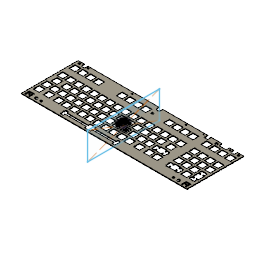
plate (Autodesk Fusion 360 design; units mm, degrees)
part number: 2025-11-08-14-59-07-070
Autodesk Fusion 360 part; units mm, degrees
(part 1 of 2)
sketch "Plate" plane through (0, 0, 0) normal (0, 0, 1) x (1, 0, 0)
  line L0 (-101.0811, -46.4126) -> (-100.2556, -46.4126)
  line L1 (-96.8806, -39.1822) -> (-96.8808, -52.6823) construction
  line L2 (-189.9049, -57.8388) -> (-189.9049, 79.958)
  line L3 (-93.5059, -43.6124) -> (-93.5059, -40.3822)
  line L4 (-100.2556, -43.6124) -> (-101.0811, -43.6124)
  line L5 (211.581, 79.958) -> (211.581, -57.8388)
  line L6 (-100.2556, -40.3822) -> (-100.2556, -43.6124)
  line L7 (-101.0811, -43.6124) -> (-101.0811, -46.4126)
  line L8 (-93.5059, -48.2122) -> (-41.481, -48.2122)
  line L9 (-41.481, -43.6124) -> (-93.5059, -43.6124)
  line L10 (25.094, -43.6124) -> (-27.3319, -43.6124)
  line L11 (-189.9049, 79.958) -> (211.581, 79.958)
  line L12 (211.581, -57.8388) -> (-189.9049, -57.8388)
  line L13 (198.458, -33.4383) -> (201.255, -33.4383)
  line L14 (196.659, -24.4124) -> (196.659, -25.8632)
  line L15 (107.469, -2.2824) -> (107.469, -5.5124)
  line L16 (192.185, -25.8632) -> (192.185, -27.5872)
  line L17 (190.986, -30.8876) -> (192.185, -30.8876)
  line L18 (204.487, -32.6129) -> (204.487, -25.8632)
  line L19 (201.255, -33.4383) -> (201.255, -32.6129)
  line L20 (115.044, -5.5124) -> (114.22, -5.5124)
  line L21 (107.469, -5.5124) -> (106.0178, -5.5124)
  line L22 (196.659, -8.8126) -> (196.659, -10.2624)
  line L23 (136.056, -33.6326) -> (137.782, -33.6326)
  line L24 (90.42, -10.1123) -> (91.8678, -10.1123)
  line L25 (135.231, -27.3626) -> (136.056, -27.3626)
  line L26 (144.2558, -24.5624) -> (142.806, -24.5624)
  line L27 (106.0178, -10.1123) -> (107.469, -10.1123)
  line L28 (204.487, -25.8632) -> (201.255, -25.8632)
  line L29 (115.044, -8.3124) -> (115.044, -5.5124)
  line L30 (31.844, -43.6124) -> (31.844, -40.3822)
  line L31 (28.469, -52.6826) -> (28.4695, -39.1822) construction
  line L32 (114.22, -2.2824) -> (107.469, -2.2824)
  line L33 (114.22, -5.5124) -> (114.22, -2.2824)
  line L34 (31.844, -46.4126) -> (32.67, -46.4126)
  line L35 (114.22, -8.3124) -> (115.044, -8.3124)
  line L36 (31.844, -52.6826) -> (31.844, -46.4126)
  line L37 (107.469, -10.1123) -> (107.469, -14.5827)
  line L38 (83.67, -2.2824) -> (83.67, -5.5124)
  line L39 (-184.3561, -19.7884) -> (-170.2053, -19.7884)
  line L40 (85.394, -14.5827) -> (85.394, -15.7828)
  line L41 (192.185, -30.8876) -> (192.185, -32.6129)
  line L42 (190.986, -27.5872) -> (190.986, -30.8876)
  line L43 (167.431, -27.3626) -> (167.431, -24.5624)
  line L44 (167.431, -24.5624) -> (166.605, -24.5624)
  line L45 (136.056, -24.5624) -> (135.231, -24.5624)
  line L46 (190.986, -3.787) -> (190.986, -7.0876)
  line L47 (161.582, -33.6326) -> (161.582, -34.8329)
  line L48 (141.082, -33.6326) -> (142.806, -33.6326)
  line L49 (142.806, -33.6326) -> (142.806, -29.1622)
  line L50 (198.458, -1.2378) -> (198.458, -2.0633)
  line L51 (85.394, -15.7828) -> (88.694, -15.7828)
  line L52 (25.094, -48.2122) -> (25.094, -52.6826)
  line L53 (88.694, -15.7828) -> (88.694, -14.5827)
  line L54 (141.082, -34.8329) -> (141.082, -33.6326)
  line L55 (82.845, -5.5124) -> (82.845, -8.3124)
  line L56 (192.185, -7.0876) -> (192.185, -8.8126)
  line L57 (136.056, -27.3626) -> (136.056, -33.6326)
  line L58 (135.231, -24.5624) -> (135.231, -27.3626)
  line L59 (32.67, -43.6124) -> (31.844, -43.6124)
  line L60 (32.67, -46.4126) -> (32.67, -43.6124)
  line L61 (112.495, -14.5827) -> (114.22, -14.5827)
  line L62 (90.42, -2.2824) -> (83.67, -2.2824)
  line L63 (201.255, -1.2378) -> (198.458, -1.2378)
  line L64 (107.469, -14.5827) -> (109.194, -14.5827)
  line L65 (204.487, -8.8126) -> (204.487, -2.0633)
  line L66 (201.255, -10.2624) -> (201.255, -8.8126)
  line L67 (159.856, -21.3324) -> (159.856, -24.5624)
  line L68 (161.582, -34.8329) -> (164.88, -34.8329)
  line L69 (90.42, -14.5827) -> (90.42, -10.1123)
  line L70 (88.694, -14.5827) -> (90.42, -14.5827)
  line L71 (83.67, -8.3124) -> (83.67, -14.5827)
  line L72 (90.42, -5.5124) -> (90.42, -2.2824)
  line L73 (-184.3562, -33.9378) -> (-184.3561, -19.7884)
  line L74 (201.255, -32.6129) -> (204.487, -32.6129)
  line L75 (190.986, -7.0876) -> (192.185, -7.0876)
  line L76 (166.605, -24.5624) -> (166.605, -21.3324)
  line L77 (91.8678, -5.5124) -> (90.42, -5.5124)
  line L78 (192.185, -32.6129) -> (198.458, -32.6129)
  line L79 (201.255, -8.8126) -> (204.487, -8.8126)
  line L80 (166.605, -27.3626) -> (167.431, -27.3626)
  line L81 (198.458, -32.6129) -> (198.458, -33.4383)
  line L82 (198.458, -2.0633) -> (192.185, -2.0633)
  line L83 (166.605, -21.3324) -> (159.856, -21.3324)
  line L84 (196.659, -25.8632) -> (192.185, -25.8632)
  line L85 (114.22, -14.5827) -> (114.22, -8.3124)
  line L86 (109.194, -14.5827) -> (109.194, -15.7828)
  line L87 (166.605, -33.6326) -> (166.605, -27.3626)
  line L88 (142.806, -21.3324) -> (136.056, -21.3324)
  line L89 (204.487, -2.0633) -> (201.255, -2.0633)
  line L90 (192.185, -27.5872) -> (190.986, -27.5872)
  line L91 (137.782, -33.6326) -> (137.782, -34.8329)
  line L92 (164.88, -34.8329) -> (164.88, -33.6326)
  line L93 (192.185, -8.8126) -> (196.659, -8.8126)
  line L94 (201.255, -2.0633) -> (201.255, -1.2378)
  line L95 (25.094, -40.3822) -> (25.094, -43.6124)
  line L96 (159.856, -29.1622) -> (159.856, -33.6326)
  line L97 (159.856, -33.6326) -> (161.582, -33.6326)
  line L98 (136.056, -21.3324) -> (136.056, -24.5624)
  line L99 (112.495, -15.7828) -> (112.495, -14.5827)
  line L100 (201.255, -25.8632) -> (201.255, -24.4124)
  line L101 (137.782, -34.8329) -> (141.082, -34.8329)
  line L102 (142.806, -24.5624) -> (142.806, -21.3324)
  line L103 (159.856, -24.5624) -> (158.4058, -24.5624)
  line L104 (142.806, -29.1622) -> (144.2558, -29.1622)
  line L105 (164.88, -33.6326) -> (166.605, -33.6326)
  line L106 (109.194, -15.7828) -> (112.495, -15.7828)
  line L107 (192.185, -3.787) -> (190.986, -3.787)
  line L108 (158.4058, -29.1622) -> (159.856, -29.1622)
  line L109 (83.67, -14.5827) -> (85.394, -14.5827)
  line L110 (192.185, -2.0633) -> (192.185, -3.787)
  line L111 (-100.2556, -46.4126) -> (-100.2556, -52.6823)
  line L112 (-100.2556, -52.6823) -> (-93.5059, -52.6824)
  line L113 (-93.5059, -52.6824) -> (-93.5059, -48.2122)
  line L114 (-170.2053, -33.9378) -> (-184.3562, -33.9378)
  line L115 (82.845, -8.3124) -> (83.67, -8.3124)
  line L116 (83.67, -5.5124) -> (82.845, -5.5124)
  line L117 (-170.2053, -19.7884) -> (-170.2053, -33.9378)
  line L118 (-175.1549, -54.3181) -> (-173.1549, -54.3181)
  line L119 (-173.1549, -43.3181) -> (-173.1549, -54.3181)
  line L120 (-189.9049, 79.958) -> (211.532, 79.958)
  arc A0 (-174.5049, 75.458) -> (-165.5049, 75.458) centre (-170.0049, 75.458) ccw
  circle A1 centre (-182.0049, 74.958) radius 2.5
  line L121 (-165.5049, 75.458) -> (-165.5049, 79.958)
  line L122 (-189.9049, 79.958) -> (211.532, 79.958)
  circle A2 centre (-161.0049, 75.458) radius 1.75
  line L123 (-174.5049, 75.458) -> (-174.5049, 79.958)
  line L124 (-175.1549, -54.3181) -> (-175.1549, -45.3181)
  line L125 (-182.6549, -54.3181) -> (-184.6549, -54.3181)
  line L126 (-184.6549, -43.3181) -> (-173.1549, -43.3181)
  line L127 (-175.1549, -45.3181) -> (-182.6549, -45.3181)
  line L128 (-182.6549, -54.3181) -> (-175.1549, -54.3181) construction
  line L129 (150.132, 70.458) -> (150.132, 75.458)
  line L130 (204.282, -54.3181) -> (204.282, -45.3181)
  line L131 (6.3721, 75.4444) -> (6.4059, 79.958)
  arc A3 (6.3721, 75.4444) -> (15.3719, 75.3774) centre (10.872, 75.4108) ccw
  line L132 (15.3719, 75.3774) -> (15.4059, 79.958)
  circle A4 centre (-178.9049, -49.3181) radius 1.75
  circle A5 centre (-54.2449, 75.458) radius 1.75
  line L133 (-184.6549, -54.3181) -> (-184.6549, -43.3181)
  line L134 (-189.9049, 79.958) -> (211.532, 79.958)
  circle A6 centre (-161.6549, -49.8181) radius 3.25
  line L135 (-189.9049, 79.958) -> (211.532, 79.958)
  line L136 (206.282, -43.3181) -> (206.282, -54.3181)
  circle A7 centre (203.632, 74.958) radius 2.5
  line L137 (187.132, 75.458) -> (187.132, 79.958)
  line L138 (173.632, 71.958) -> (161.632, 71.958)
  arc A8 (187.132, 75.458) -> (196.132, 75.458) centre (191.632, 75.458) ccw
  line L139 (150.132, 75.458) -> (155.132, 75.458)
  arc A9 (173.632, 71.958) -> (176.632, 74.958) centre (173.632, 74.958) ccw
  circle A10 centre (75.872, 75.458) radius 1.75
  line L140 (132.432, 71) -> (124.432, 71)
  line L141 (124.432, 80) -> (132.432, 80)
  line L142 (132.432, 80) -> (132.432, 71)
  circle A11 centre (117.432, 76.708) radius 1.25
  line L143 (155.132, 70.458) -> (150.132, 70.458)
  line L144 (124.432, 71) -> (124.432, 80)
  circle A12 centre (183.282, -49.8181) radius 3.25
  line L145 (176.632, 79.958) -> (176.632, 74.958)
  circle A13 centre (182.632, 75.458) radius 1.75
  line L146 (196.132, 75.458) -> (196.132, 79.958)
  line L147 (158.632, 74.958) -> (158.632, 79.958)
  line L148 (155.132, 75.458) -> (155.132, 70.458)
  arc A14 (158.632, 74.958) -> (161.632, 71.958) centre (161.632, 74.958) ccw
  line L149 (196.782, -54.3181) -> (194.782, -54.3181)
  line L150 (194.782, -43.3181) -> (206.282, -43.3181)
  line L151 (196.782, -45.3181) -> (196.782, -54.3181)
  line L152 (204.282, -45.3181) -> (196.782, -45.3181)
  circle A15 centre (200.532, -49.3181) radius 1.75
  line L153 (-182.6549, -45.3181) -> (-182.6549, -54.3181)
  line L154 (196.782, -54.3181) -> (204.282, -54.3181) construction
  line L155 (206.282, -54.3181) -> (204.282, -54.3181)
  line L156 (194.782, -54.3181) -> (194.782, -43.3181)
  line L157 (-170.2062, 66.925) -> (-184.3562, 66.925)
  line L158 (-184.3562, 66.925) -> (-184.3562, 52.775)
  line L159 (-184.3562, 52.775) -> (-170.2062, 52.775)
  line L160 (-170.2062, 52.775) -> (-170.2062, 66.925)
  line L161 (-170.2062, 66.925) -> (-184.3562, 52.775) construction
  line L162 (-184.3562, 66.925) -> (-170.2062, 52.775) construction
  line L163 (-170.2062, 23.2116) -> (-170.2062, 37.3616)
  line L164 (-184.3562, 37.3616) -> (-184.3562, 23.2116)
  line L165 (-170.2062, 37.3616) -> (-184.3562, 37.3616)
  line L166 (-170.2062, 37.3616) -> (-184.3562, 23.2116) construction
  line L167 (-184.3562, 37.3616) -> (-170.2062, 23.2116) construction
  line L168 (-184.3562, 23.2116) -> (-170.2062, 23.2116)
  line L169 (-179.5739, 18.3116) -> (-165.4239, 4.1616) construction
  line L170 (-165.4239, 18.3116) -> (-179.5739, 4.1616) construction
  line L171 (-179.5739, 4.1616) -> (-165.4239, 4.1616)
  line L172 (-165.4239, 4.1616) -> (-165.4239, 18.3116)
  line L173 (-179.5739, 18.3116) -> (-179.5739, 4.1616)
  line L174 (-165.4239, 18.3116) -> (-179.5739, 18.3116)
  line L175 (-165.3062, 66.925) -> (-165.3062, 52.775)
  line L176 (-151.1562, 66.925) -> (-165.3062, 66.925)
  line L177 (-165.3062, 52.775) -> (-151.1562, 52.775)
  line L178 (-151.1562, 52.775) -> (-151.1562, 66.925)
  line L179 (-165.3062, 66.925) -> (-151.1562, 52.775) construction
  line L180 (-151.1562, 66.925) -> (-165.3062, 52.775) construction
  line L181 (-146.2562, 66.925) -> (-146.2562, 52.775)
  line L182 (-132.1062, 66.925) -> (-146.2562, 66.925)
  line L183 (-146.2562, 52.775) -> (-132.1062, 52.775)
  line L184 (-132.1062, 52.775) -> (-132.1062, 66.925)
  line L185 (-146.2562, 66.925) -> (-132.1062, 52.775) construction
  line L186 (-132.1062, 66.925) -> (-146.2562, 52.775) construction
  line L187 (-127.2062, 66.925) -> (-127.2062, 52.775)
  line L188 (-113.0562, 66.925) -> (-127.2062, 66.925)
  line L189 (-127.2062, 52.775) -> (-113.0562, 52.775)
  line L190 (-113.0562, 52.775) -> (-113.0562, 66.925)
  line L191 (-127.2062, 66.925) -> (-113.0562, 52.775) construction
  line L192 (-113.0562, 66.925) -> (-127.2062, 52.775) construction
  line L193 (-113.0562, 66.925) -> (-127.2062, 66.925)
  line L194 (-127.2062, 52.775) -> (-113.0562, 52.775)
  line L195 (-165.3062, 52.775) -> (-151.1562, 52.775)
  line L196 (-170.2062, 66.925) -> (-184.3562, 66.925)
  line L197 (-151.1562, 66.925) -> (-165.3062, 52.775) construction
  line L198 (-184.3562, 66.925) -> (-184.3562, 52.775)
  line L199 (-132.1062, 66.925) -> (-146.2562, 66.925)
  line L200 (-132.1062, 66.925) -> (-146.2562, 52.775) construction
  line L201 (-146.2562, 66.925) -> (-146.2562, 52.775)
  line L202 (-165.3062, 66.925) -> (-151.1562, 52.775) construction
  line L203 (-127.2062, 66.925) -> (-113.0562, 52.775) construction
  line L204 (-184.3562, 52.775) -> (-170.2062, 52.775)
  line L205 (-165.3062, 66.925) -> (-165.3062, 52.775)
  line L206 (-170.2062, 52.775) -> (-170.2062, 66.925)
  line L207 (-146.2562, 66.925) -> (-132.1062, 52.775) construction
  line L208 (-113.0562, 52.775) -> (-113.0562, 66.925)
  line L209 (-113.0562, 66.925) -> (-127.2062, 52.775) construction
  line L210 (-127.2062, 66.925) -> (-127.2062, 52.775)
  line L211 (-132.1062, 52.775) -> (-132.1062, 66.925)
  line L212 (-146.2562, 52.775) -> (-132.1062, 52.775)
  line L213 (-151.1562, 66.925) -> (-165.3062, 66.925)
  line L214 (-170.2062, 66.925) -> (-184.3562, 52.775) construction
  line L215 (-151.1562, 52.775) -> (-151.1562, 66.925)
  line L216 (-184.3562, 66.925) -> (-170.2062, 52.775) construction
  line L217 (1.2438, 52.775) -> (1.2438, 66.925)
  line L218 (-31.9562, 52.775) -> (-17.8062, 52.775)
  line L219 (1.2438, 66.925) -> (-12.9062, 52.775) construction
  line L220 (-36.8562, 66.925) -> (-51.0062, 52.775) construction
  line L221 (-36.8562, 66.925) -> (-51.0062, 66.925)
  line L222 (-55.9062, 66.925) -> (-70.0562, 66.925)
  line L223 (-55.9062, 52.775) -> (-55.9062, 66.925)
  line L224 (-17.8062, 66.925) -> (-31.9562, 66.925)
  line L225 (-12.9062, 52.775) -> (1.2438, 52.775)
  line L226 (-51.0062, 66.925) -> (-36.8562, 52.775) construction
  line L227 (-51.0062, 52.775) -> (-36.8562, 52.775)
  line L228 (-36.8562, 66.925) -> (-51.0062, 52.775) construction
  line L229 (-51.0062, 66.925) -> (-36.8562, 52.775) construction
  line L230 (-12.9062, 66.925) -> (1.2438, 52.775) construction
  line L231 (-17.8062, 66.925) -> (-31.9562, 66.925)
  line L232 (1.2438, 66.925) -> (-12.9062, 66.925)
  line L233 (-36.8562, 52.775) -> (-36.8562, 66.925)
  line L234 (-70.0562, 52.775) -> (-55.9062, 52.775)
  line L235 (-55.9062, 52.775) -> (-55.9062, 66.925)
  line L236 (-70.0562, 66.925) -> (-70.0562, 52.775)
  line L237 (-36.8562, 52.775) -> (-36.8562, 66.925)
  line L238 (-55.9062, 66.925) -> (-70.0562, 66.925)
  line L239 (-70.0562, 66.925) -> (-70.0562, 52.775)
  line L240 (-51.0062, 66.925) -> (-51.0062, 52.775)
  line L241 (1.2438, 52.775) -> (1.2438, 66.925)
  line L242 (-17.8062, 52.775) -> (-17.8062, 66.925)
  line L243 (-70.0562, 66.925) -> (-55.9062, 52.775) construction
  line L244 (-12.9062, 66.925) -> (1.2438, 52.775) construction
  line L245 (-12.9062, 66.925) -> (-12.9062, 52.775)
  line L246 (-55.9062, 66.925) -> (-70.0562, 52.775) construction
  line L247 (-70.0562, 66.925) -> (-55.9062, 52.775) construction
  line L248 (-55.9062, 66.925) -> (-70.0562, 52.775) construction
  line L249 (-17.8062, 52.775) -> (-17.8062, 66.925)
  line L250 (1.2438, 66.925) -> (-12.9062, 52.775) construction
  line L251 (-12.9062, 52.775) -> (1.2438, 52.775)
  line L252 (-12.9062, 66.925) -> (-12.9062, 52.775)
  line L253 (-31.9562, 66.925) -> (-17.8062, 52.775) construction
  line L254 (-17.8062, 66.925) -> (-31.9562, 52.775) construction
  line L255 (1.2438, 66.925) -> (-12.9062, 66.925)
  line L256 (-17.8062, 66.925) -> (-31.9562, 52.775) construction
  line L257 (-31.9562, 52.775) -> (-17.8062, 52.775)
  line L258 (-31.9562, 66.925) -> (-17.8062, 52.775) construction
  line L259 (-51.0062, 52.775) -> (-36.8562, 52.775)
  line L260 (-70.0562, 52.775) -> (-55.9062, 52.775)
  line L261 (-36.8562, 66.925) -> (-51.0062, 66.925)
  line L262 (-31.9562, 66.925) -> (-31.9562, 52.775)
  line L263 (-51.0062, 66.925) -> (-51.0062, 52.775)
  line L264 (-31.9562, 66.925) -> (-31.9562, 52.775)
  line L265 (115.5438, 52.775) -> (115.5438, 66.925)
  line L266 (82.3438, 52.775) -> (96.4938, 52.775)
  line L267 (115.5438, 66.925) -> (101.3938, 52.775) construction
  line L268 (77.4438, 66.925) -> (63.2938, 52.775) construction
  line L269 (77.4438, 66.925) -> (63.2938, 66.925)
  line L270 (58.3938, 66.925) -> (44.2438, 66.925)
  line L271 (58.3938, 52.775) -> (58.3938, 66.925)
  line L272 (96.4938, 66.925) -> (82.3438, 66.925)
  line L273 (101.3938, 52.775) -> (115.5438, 52.775)
  line L274 (63.2938, 66.925) -> (77.4438, 52.775) construction
  line L275 (63.2938, 52.775) -> (77.4438, 52.775)
  line L276 (77.4438, 66.925) -> (63.2938, 52.775) construction
  line L277 (63.2938, 66.925) -> (77.4438, 52.775) construction
  line L278 (101.3938, 66.925) -> (115.5438, 52.775) construction
  line L279 (96.4938, 66.925) -> (82.3438, 66.925)
  line L280 (115.5438, 66.925) -> (101.3938, 66.925)
  line L281 (77.4438, 52.775) -> (77.4438, 66.925)
  line L282 (44.2438, 52.775) -> (58.3938, 52.775)
  line L283 (58.3938, 52.775) -> (58.3938, 66.925)
  line L284 (44.2438, 66.925) -> (44.2438, 52.775)
  line L285 (77.4438, 52.775) -> (77.4438, 66.925)
  line L286 (58.3938, 66.925) -> (44.2438, 66.925)
  line L287 (44.2438, 66.925) -> (44.2438, 52.775)
  line L288 (63.2938, 66.925) -> (63.2938, 52.775)
  line L289 (115.5438, 52.775) -> (115.5438, 66.925)
  line L290 (96.4938, 52.775) -> (96.4938, 66.925)
  line L291 (44.2438, 66.925) -> (58.3938, 52.775) construction
  line L292 (101.3938, 66.925) -> (115.5438, 52.775) construction
  line L293 (101.3938, 66.925) -> (101.3938, 52.775)
  line L294 (58.3938, 66.925) -> (44.2438, 52.775) construction
  line L295 (44.2438, 66.925) -> (58.3938, 52.775) construction
  line L296 (58.3938, 66.925) -> (44.2438, 52.775) construction
  line L297 (96.4938, 52.775) -> (96.4938, 66.925)
  line L298 (115.5438, 66.925) -> (101.3938, 52.775) construction
  line L299 (101.3938, 52.775) -> (115.5438, 52.775)
  line L300 (101.3938, 66.925) -> (101.3938, 52.775)
  line L301 (82.3438, 66.925) -> (96.4938, 52.775) construction
  line L302 (96.4938, 66.925) -> (82.3438, 52.775) construction
  line L303 (115.5438, 66.925) -> (101.3938, 66.925)
  line L304 (96.4938, 66.925) -> (82.3438, 52.775) construction
  line L305 (82.3438, 52.775) -> (96.4938, 52.775)
  line L306 (82.3438, 66.925) -> (96.4938, 52.775) construction
  line L307 (63.2938, 52.775) -> (77.4438, 52.775)
  line L308 (44.2438, 52.775) -> (58.3938, 52.775)
  line L309 (77.4438, 66.925) -> (63.2938, 66.925)
  line L310 (82.3438, 66.925) -> (82.3438, 52.775)
  line L311 (63.2938, 66.925) -> (63.2938, 52.775)
  line L312 (82.3438, 66.925) -> (82.3438, 52.775)
  line L313 (148.8798, 66.925) -> (134.7298, 66.925)
  line L314 (153.7798, 52.775) -> (167.9298, 52.775)
  line L315 (167.9298, 66.925) -> (153.7798, 52.775) construction
  line L316 (206.0298, 52.775) -> (206.0298, 66.925)
  line L317 (153.7798, 66.925) -> (153.7798, 52.775)
  line L318 (191.8798, 66.925) -> (206.0298, 52.775) construction
  line L319 (186.9798, 52.775) -> (186.9798, 66.925)
  line L320 (191.8798, 66.925) -> (191.8798, 52.775)
  line L321 (153.7798, 66.925) -> (153.7798, 52.775)
  line L322 (153.7798, 66.925) -> (167.9298, 52.775) construction
  line L323 (191.8798, 66.925) -> (206.0298, 52.775) construction
  line L324 (167.9298, 52.775) -> (167.9298, 66.925)
  line L325 (148.8798, 52.775) -> (148.8798, 66.925)
  line L326 (206.0298, 66.925) -> (191.8798, 52.775) construction
  line L327 (172.8298, 66.925) -> (172.8298, 52.775)
  line L328 (167.9298, 52.775) -> (167.9298, 66.925)
  line L329 (206.0298, 66.925) -> (191.8798, 52.775) construction
  line L330 (191.8798, 66.925) -> (191.8798, 52.775)
  line L331 (153.7798, 66.925) -> (167.9298, 52.775) construction
  line L332 (186.9798, 66.925) -> (172.8298, 66.925)
  line L333 (167.9298, 66.925) -> (153.7798, 66.925)
  line L334 (191.8798, 52.775) -> (206.0298, 52.775)
  line L335 (186.9798, 52.775) -> (186.9798, 66.925)
  line L336 (206.0298, 66.925) -> (191.8798, 66.925)
  line L337 (134.7298, 66.925) -> (148.8798, 52.775) construction
  line L338 (206.0298, 52.775) -> (206.0298, 66.925)
  line L339 (186.9798, 66.925) -> (172.8298, 52.775) construction
  line L340 (206.0298, 66.925) -> (191.8798, 66.925)
  line L341 (172.8298, 52.775) -> (186.9798, 52.775)
  line L342 (172.8298, 66.925) -> (186.9798, 52.775) construction
  line L343 (134.7298, 52.775) -> (148.8798, 52.775)
  line L344 (167.9298, 66.925) -> (153.7798, 52.775) construction
  line L345 (148.8798, 52.775) -> (148.8798, 66.925)
  line L346 (134.7298, 66.925) -> (148.8798, 52.775) construction
  line L347 (134.7298, 66.925) -> (134.7298, 52.775)
  line L348 (191.8798, 52.775) -> (206.0298, 52.775)
  line L349 (148.8798, 66.925) -> (134.7298, 52.775) construction
  line L350 (134.7298, 66.925) -> (134.7298, 52.775)
  line L351 (134.7298, 52.775) -> (148.8798, 52.775)
  line L352 (172.8298, 66.925) -> (186.9798, 52.775) construction
  line L353 (148.8798, 66.925) -> (134.7298, 52.775) construction
  line L354 (172.8298, 66.925) -> (172.8298, 52.775)
  line L355 (153.7798, 52.775) -> (167.9298, 52.775)
  line L356 (186.9798, 66.925) -> (172.8298, 52.775) construction
  line L357 (167.9298, 66.925) -> (153.7798, 66.925)
  line L358 (172.8298, 52.775) -> (186.9798, 52.775)
  line L359 (186.9798, 66.925) -> (172.8298, 66.925)
  line L360 (148.8798, 66.925) -> (134.7298, 66.925)
  line L361 (-151.1562, 37.3616) -> (-165.3062, 23.2116) construction
  line L362 (-165.3062, 37.3616) -> (-151.1562, 23.2116) construction
  line L363 (-151.1562, 37.3616) -> (-165.3062, 37.3616)
  line L364 (-165.3062, 23.2116) -> (-151.1562, 23.2116)
  line L365 (-165.3062, 37.3616) -> (-165.3062, 23.2116)
  line L366 (-151.1562, 23.2116) -> (-151.1562, 37.3616)
  line L367 (-132.1062, 37.3616) -> (-146.2562, 23.2116) construction
  line L368 (-146.2562, 37.3616) -> (-132.1062, 23.2116) construction
  line L369 (-132.1062, 37.3616) -> (-146.2562, 37.3616)
  line L370 (-146.2562, 23.2116) -> (-132.1062, 23.2116)
  line L371 (-146.2562, 37.3616) -> (-146.2562, 23.2116)
  line L372 (-132.1062, 23.2116) -> (-132.1062, 37.3616)
  line L373 (-113.0562, 37.3616) -> (-127.2062, 23.2116) construction
  line L374 (-127.2062, 37.3616) -> (-113.0562, 23.2116) construction
  line L375 (-113.0562, 37.3616) -> (-127.2062, 37.3616)
  line L376 (-127.2062, 23.2116) -> (-113.0562, 23.2116)
  line L377 (-127.2062, 37.3616) -> (-127.2062, 23.2116)
  line L378 (-113.0562, 23.2116) -> (-113.0562, 37.3616)
  line L379 (-94.0062, 37.3616) -> (-108.1562, 23.2116) construction
  line L380 (-108.1562, 37.3616) -> (-94.0062, 23.2116) construction
  line L381 (-94.0062, 37.3616) -> (-108.1562, 37.3616)
  line L382 (-108.1562, 23.2116) -> (-94.0062, 23.2116)
  line L383 (-108.1562, 37.3616) -> (-108.1562, 23.2116)
  line L384 (-94.0062, 23.2116) -> (-94.0062, 37.3616)
  line L385 (-74.9562, 37.3616) -> (-89.1062, 23.2116) construction
  line L386 (-89.1062, 37.3616) -> (-74.9562, 23.2116) construction
  line L387 (-74.9562, 37.3616) -> (-89.1062, 37.3616)
  line L388 (-89.1062, 23.2116) -> (-74.9562, 23.2116)
  line L389 (-89.1062, 37.3616) -> (-89.1062, 23.2116)
  line L390 (-74.9562, 23.2116) -> (-74.9562, 37.3616)
  line L391 (-55.9062, 37.3616) -> (-70.0562, 23.2116) construction
  line L392 (-70.0562, 37.3616) -> (-55.9062, 23.2116) construction
  line L393 (-55.9062, 37.3616) -> (-70.0562, 37.3616)
  line L394 (-70.0562, 23.2116) -> (-55.9062, 23.2116)
  line L395 (-70.0562, 37.3616) -> (-70.0562, 23.2116)
  line L396 (-55.9062, 23.2116) -> (-55.9062, 37.3616)
  line L397 (-36.8562, 37.3616) -> (-51.0062, 23.2116) construction
  line L398 (-51.0062, 37.3616) -> (-36.8562, 23.2116) construction
  line L399 (-36.8562, 37.3616) -> (-51.0062, 37.3616)
  line L400 (-51.0062, 23.2116) -> (-36.8562, 23.2116)
  line L401 (-51.0062, 37.3616) -> (-51.0062, 23.2116)
  line L402 (-36.8562, 23.2116) -> (-36.8562, 37.3616)
  line L403 (-17.8062, 37.3616) -> (-31.9562, 23.2116) construction
  line L404 (-31.9562, 37.3616) -> (-17.8062, 23.2116) construction
  line L405 (-17.8062, 37.3616) -> (-31.9562, 37.3616)
  line L406 (-31.9562, 23.2116) -> (-17.8062, 23.2116)
  line L407 (-31.9562, 37.3616) -> (-31.9562, 23.2116)
  line L408 (-17.8062, 23.2116) -> (-17.8062, 37.3616)
  line L409 (1.2438, 37.3616) -> (-12.9062, 23.2116) construction
  line L410 (-12.9062, 37.3616) -> (1.2438, 23.2116) construction
  line L411 (1.2438, 37.3616) -> (-12.9062, 37.3616)
  line L412 (-12.9062, 23.2116) -> (1.2438, 23.2116)
  line L413 (-12.9062, 37.3616) -> (-12.9062, 23.2116)
  line L414 (1.2438, 23.2116) -> (1.2438, 37.3616)
  line L415 (20.2938, 37.3616) -> (6.1438, 23.2116) construction
  line L416 (6.1438, 37.3616) -> (20.2938, 23.2116) construction
  line L417 (20.2938, 37.3616) -> (6.1438, 37.3616)
  line L418 (6.1438, 23.2116) -> (20.2938, 23.2116)
  line L419 (6.1438, 37.3616) -> (6.1438, 23.2116)
  line L420 (20.2938, 23.2116) -> (20.2938, 37.3616)
  line L421 (39.3438, 37.3616) -> (25.1938, 23.2116) construction
  line L422 (25.1938, 37.3616) -> (39.3438, 23.2116) construction
  line L423 (39.3438, 37.3616) -> (25.1938, 37.3616)
  line L424 (25.1938, 23.2116) -> (39.3438, 23.2116)
  line L425 (25.1938, 37.3616) -> (25.1938, 23.2116)
  line L426 (39.3438, 23.2116) -> (39.3438, 37.3616)
  line L427 (58.3938, 37.3616) -> (44.2438, 23.2116) construction
  line L428 (44.2438, 37.3616) -> (58.3938, 23.2116) construction
  line L429 (58.3938, 37.3616) -> (44.2438, 37.3616)
  line L430 (44.2438, 23.2116) -> (58.3938, 23.2116)
  line L431 (44.2438, 37.3616) -> (44.2438, 23.2116)
  line L432 (58.3938, 23.2116) -> (58.3938, 37.3616)
  line L433 (77.4438, 37.3616) -> (63.2938, 23.2116) construction
  line L434 (63.2938, 37.3616) -> (77.4438, 23.2116) construction
  line L435 (77.4438, 37.3616) -> (63.2938, 37.3616)
  line L436 (63.2938, 23.2116) -> (77.4438, 23.2116)
  line L437 (63.2938, 37.3616) -> (63.2938, 23.2116)
  line L438 (77.4438, 23.2116) -> (77.4438, 37.3616)
  line L439 (96.4938, 37.3616) -> (82.3438, 23.2116) construction
  line L440 (82.3438, 37.3616) -> (96.4938, 23.2116) construction
  line L441 (96.4938, 37.3616) -> (82.3438, 37.3616)
  line L442 (82.3438, 23.2116) -> (96.4938, 23.2116)
  line L443 (82.3438, 37.3616) -> (82.3438, 23.2116)
  line L444 (96.4938, 23.2116) -> (96.4938, 37.3616)
  line L445 (115.5438, 37.3616) -> (101.3938, 23.2116) construction
  line L446 (101.3938, 37.3616) -> (115.5438, 23.2116) construction
  line L447 (115.5438, 37.3616) -> (101.3938, 37.3616)
  line L448 (101.3938, 23.2116) -> (115.5438, 23.2116)
  line L449 (101.3938, 37.3616) -> (101.3938, 23.2116)
  line L450 (115.5438, 23.2116) -> (115.5438, 37.3616)
  line L451 (148.8798, 37.3616) -> (134.7298, 23.2116) construction
  line L452 (186.9798, 37.3616) -> (172.8298, 37.3616)
  line L453 (134.7298, 37.3616) -> (148.8798, 23.2116) construction
  line L454 (153.7798, 37.3616) -> (153.7798, 23.2116)
  line L455 (172.8298, 37.3616) -> (186.9798, 23.2116) construction
  line L456 (153.7798, 23.2116) -> (167.9298, 23.2116)
  line L457 (186.9798, 37.3616) -> (172.8298, 23.2116) construction
  line L458 (186.9798, 23.2116) -> (186.9798, 37.3616)
  line L459 (191.8798, 37.3616) -> (191.8798, 23.2116)
  line L460 (206.0298, 23.2116) -> (206.0298, 37.3616)
  line L461 (148.8798, 37.3616) -> (134.7298, 37.3616)
  line L462 (167.9298, 23.2116) -> (167.9298, 37.3616)
  line L463 (191.8798, 23.2116) -> (206.0298, 23.2116)
  line L464 (206.0298, 37.3616) -> (191.8798, 23.2116) construction
  line L465 (153.7798, 37.3616) -> (167.9298, 23.2116) construction
  line L466 (206.0298, 37.3616) -> (191.8798, 37.3616)
  line L467 (191.8798, 37.3616) -> (206.0298, 23.2116) construction
  line L468 (172.8298, 23.2116) -> (186.9798, 23.2116)
  line L469 (134.7298, 23.2116) -> (148.8798, 23.2116)
  line L470 (134.7298, 37.3616) -> (134.7298, 23.2116)
  line L471 (167.9298, 37.3616) -> (153.7798, 23.2116) construction
  line L472 (167.9298, 37.3616) -> (153.7798, 37.3616)
  line L473 (148.8798, 23.2116) -> (148.8798, 37.3616)
  line L474 (172.8298, 37.3616) -> (172.8298, 23.2116)
  line L475 (-155.7819, 18.3116) -> (-155.7819, 4.1616)
  line L476 (-141.6319, 4.1616) -> (-141.6319, 18.3116)
  line L477 (-141.6319, 18.3116) -> (-155.7819, 4.1616) construction
  line L478 (-155.7819, 4.1616) -> (-141.6319, 4.1616)
  line L479 (-141.6319, 18.3116) -> (-155.7819, 18.3116)
  line L480 (-155.7819, 18.3116) -> (-141.6319, 4.1616) construction
  line L481 (-122.5819, 18.3116) -> (-136.7319, 4.1616) construction
  line L482 (-122.5819, 4.1616) -> (-122.5819, 18.3116)
  line L483 (-122.5819, 18.3116) -> (-136.7319, 18.3116)
  line L484 (-136.7319, 4.1616) -> (-122.5819, 4.1616)
  line L485 (-136.7319, 18.3116) -> (-122.5819, 4.1616) construction
  line L486 (-136.7319, 18.3116) -> (-136.7319, 4.1616)
  line L487 (-103.5319, 18.3116) -> (-117.6819, 4.1616) construction
  line L488 (-103.5319, 4.1616) -> (-103.5319, 18.3116)
  line L489 (-103.5319, 18.3116) -> (-117.6819, 18.3116)
  line L490 (-117.6819, 4.1616) -> (-103.5319, 4.1616)
  line L491 (-117.6819, 18.3116) -> (-103.5319, 4.1616) construction
  line L492 (-117.6819, 18.3116) -> (-117.6819, 4.1616)
  line L493 (-84.4819, 18.3116) -> (-98.6319, 4.1616) construction
  line L494 (-84.4819, 4.1616) -> (-84.4819, 18.3116)
  line L495 (-84.4819, 18.3116) -> (-98.6319, 18.3116)
  line L496 (-98.6319, 4.1616) -> (-84.4819, 4.1616)
  line L497 (-98.6319, 18.3116) -> (-84.4819, 4.1616) construction
  line L498 (-98.6319, 18.3116) -> (-98.6319, 4.1616)
  line L499 (-65.4319, 18.3116) -> (-79.5819, 4.1616) construction
  line L500 (-65.4319, 4.1616) -> (-65.4319, 18.3116)
  line L501 (-65.4319, 18.3116) -> (-79.5819, 18.3116)
  line L502 (-79.5819, 4.1616) -> (-65.4319, 4.1616)
  line L503 (-79.5819, 18.3116) -> (-65.4319, 4.1616) construction
  line L504 (-79.5819, 18.3116) -> (-79.5819, 4.1616)
  line L505 (-46.3819, 18.3116) -> (-60.5319, 4.1616) construction
  line L506 (-46.3819, 4.1616) -> (-46.3819, 18.3116)
  line L507 (-46.3819, 18.3116) -> (-60.5319, 18.3116)
  line L508 (-60.5319, 4.1616) -> (-46.3819, 4.1616)
  line L509 (-60.5319, 18.3116) -> (-46.3819, 4.1616) construction
  line L510 (-60.5319, 18.3116) -> (-60.5319, 4.1616)
  line L511 (-27.3319, 18.3116) -> (-41.4819, 4.1616) construction
  line L512 (-27.3319, 4.1616) -> (-27.3319, 18.3116)
  line L513 (-27.3319, 18.3116) -> (-41.4819, 18.3116)
  line L514 (-41.4819, 4.1616) -> (-27.3319, 4.1616)
  line L515 (-41.4819, 18.3116) -> (-27.3319, 4.1616) construction
  line L516 (-41.4819, 18.3116) -> (-41.4819, 4.1616)
  line L517 (-8.2819, 18.3116) -> (-22.4319, 4.1616) construction
  line L518 (-8.2819, 4.1616) -> (-8.2819, 18.3116)
  line L519 (-8.2819, 18.3116) -> (-22.4319, 18.3116)
  line L520 (-22.4319, 4.1616) -> (-8.2819, 4.1616)
  line L521 (-22.4319, 18.3116) -> (-8.2819, 4.1616) construction
  line L522 (-22.4319, 18.3116) -> (-22.4319, 4.1616)
  line L523 (10.7681, 18.3116) -> (-3.3819, 4.1616) construction
  line L524 (10.7681, 4.1616) -> (10.7681, 18.3116)
  line L525 (10.7681, 18.3116) -> (-3.3819, 18.3116)
  line L526 (-3.3819, 4.1616) -> (10.7681, 4.1616)
  line L527 (-3.3819, 18.3116) -> (10.7681, 4.1616) construction
  line L528 (-3.3819, 18.3116) -> (-3.3819, 4.1616)
  line L529 (29.8181, 18.3116) -> (15.6681, 4.1616) construction
  line L530 (29.8181, 4.1616) -> (29.8181, 18.3116)
  line L531 (29.8181, 18.3116) -> (15.6681, 18.3116)
  line L532 (15.6681, 4.1616) -> (29.8181, 4.1616)
  line L533 (15.6681, 18.3116) -> (29.8181, 4.1616) construction
  line L534 (15.6681, 18.3116) -> (15.6681, 4.1616)
  line L535 (48.8681, 18.3116) -> (34.7181, 4.1616) construction
  line L536 (48.8681, 4.1616) -> (48.8681, 18.3116)
  line L537 (48.8681, 18.3116) -> (34.7181, 18.3116)
  line L538 (34.7181, 4.1616) -> (48.8681, 4.1616)
  line L539 (34.7181, 18.3116) -> (48.8681, 4.1616) construction
  line L540 (34.7181, 18.3116) -> (34.7181, 4.1616)
  line L541 (67.9181, 18.3116) -> (53.7681, 4.1616) construction
  line L542 (67.9181, 4.1616) -> (67.9181, 18.3116)
  line L543 (67.9181, 18.3116) -> (53.7681, 18.3116)
  line L544 (53.7681, 4.1616) -> (67.9181, 4.1616)
  line L545 (53.7681, 18.3116) -> (67.9181, 4.1616) construction
  line L546 (53.7681, 18.3116) -> (53.7681, 4.1616)
  line L547 (86.9681, 18.3116) -> (72.8181, 4.1616) construction
  line L548 (86.9681, 4.1616) -> (86.9681, 18.3116)
  line L549 (86.9681, 18.3116) -> (72.8181, 18.3116)
  line L550 (72.8181, 4.1616) -> (86.9681, 4.1616)
  line L551 (72.8181, 18.3116) -> (86.9681, 4.1616) construction
  line L552 (72.8181, 18.3116) -> (72.8181, 4.1616)
  line L553 (96.6311, 18.3116) -> (110.7811, 4.1616) construction
  line L554 (96.6311, 18.3116) -> (96.6311, 4.1616)
  line L555 (110.7811, 18.3116) -> (96.6311, 18.3116)
  line L556 (110.7811, 18.3116) -> (96.6311, 4.1616) construction
  line L557 (96.6311, 4.1616) -> (110.7811, 4.1616)
  line L558 (110.7811, 4.1616) -> (110.7811, 18.3116)
  line L559 (148.8798, 18.3116) -> (134.7298, 4.1616) construction
  line L560 (134.7298, 18.3116) -> (148.8798, 4.1616) construction
  line L561 (148.8798, 4.1616) -> (148.8798, 18.3116)
  line L562 (167.9298, 4.1616) -> (167.9298, 18.3116)
  line L563 (134.7298, 4.1616) -> (148.8798, 4.1616)
  line L564 (167.9298, 18.3116) -> (153.7798, 4.1616) construction
  line L565 (153.7798, 18.3116) -> (167.9298, 4.1616) construction
  line L566 (153.7798, 18.3116) -> (153.7798, 4.1616)
  line L567 (134.7298, 18.3116) -> (134.7298, 4.1616)
  line L568 (167.9298, 18.3116) -> (153.7798, 18.3116)
  line L569 (153.7798, 4.1616) -> (167.9298, 4.1616)
  line L570 (148.8798, 18.3116) -> (134.7298, 18.3116)
  line L571 (148.8798, -0.7384) -> (134.7298, -14.8884) construction
  line L572 (134.7298, -0.7384) -> (148.8798, -14.8884) construction
  line L573 (148.8798, -14.8884) -> (148.8798, -0.7384)
  line L574 (167.9298, -14.8884) -> (167.9298, -0.7384)
  line L575 (134.7298, -14.8884) -> (148.8798, -14.8884)
  line L576 (167.9298, -0.7384) -> (153.7798, -14.8884) construction
  line L577 (153.7798, -0.7384) -> (167.9298, -14.8884) construction
  line L578 (153.7798, -0.7384) -> (153.7798, -14.8884)
  line L579 (134.7298, -0.7384) -> (134.7298, -14.8884)
  line L580 (167.9298, -0.7384) -> (153.7798, -0.7384)
  line L581 (153.7798, -14.8884) -> (167.9298, -14.8884)
  line L582 (148.8798, -0.7384) -> (134.7298, -0.7384)
  line L583 (186.9798, 4.1616) -> (186.9798, 18.3116)
  line L584 (172.8298, 4.1616) -> (186.9798, 4.1616)
  line L585 (186.9798, 18.3116) -> (172.8298, 4.1616) construction
  line L586 (172.8298, 18.3116) -> (172.8298, 4.1616)
  line L587 (172.8298, 18.3116) -> (186.9798, 4.1616) construction
  line L588 (186.9798, 18.3116) -> (172.8298, 18.3116)
  line L589 (186.9798, -14.8884) -> (186.9798, -0.7384)
  line L590 (172.8298, -14.8884) -> (186.9798, -14.8884)
  line L591 (186.9798, -0.7384) -> (172.8298, -14.8884) construction
  line L592 (172.8298, -0.7384) -> (172.8298, -14.8884)
  line L593 (172.8298, -0.7384) -> (186.9798, -14.8884) construction
  line L594 (186.9798, -0.7384) -> (172.8298, -0.7384)
  line L595 (186.9798, -33.9384) -> (186.9798, -19.7884)
  line L596 (172.8298, -33.9384) -> (186.9798, -33.9384)
  line L597 (186.9798, -19.7884) -> (172.8298, -33.9384) construction
  line L598 (172.8298, -19.7884) -> (172.8298, -33.9384)
  line L599 (172.8298, -19.7884) -> (186.9798, -33.9384) construction
  line L600 (186.9798, -19.7884) -> (172.8298, -19.7884)
  line L601 (206.0298, 4.1616) -> (206.0298, 18.3116)
  line L602 (191.8798, 18.3116) -> (191.8798, 4.1616)
  line L603 (206.0298, 18.3116) -> (191.8798, 18.3116)
  line L604 (191.8798, 18.3116) -> (206.0298, 4.1616) construction
  line L605 (191.8798, 4.1616) -> (206.0298, 4.1616)
  line L606 (206.0298, 18.3116) -> (191.8798, 4.1616) construction
  line L607 (6.1438, -14.8884) -> (20.2938, -14.8884)
  line L608 (-108.1562, -0.7384) -> (-94.0062, -14.8884) construction
  line L609 (-108.1562, -14.8884) -> (-94.0062, -14.8884)
  line L610 (20.2938, -0.7384) -> (6.1438, -14.8884) construction
  line L611 (-94.0062, -14.8884) -> (-94.0062, -0.7384)
  line L612 (-94.0062, -0.7384) -> (-108.1562, -0.7384)
  line L613 (6.1438, -0.7384) -> (20.2938, -14.8884) construction
  line L614 (-94.0062, -0.7384) -> (-108.1562, -14.8884) construction
  line L615 (20.2938, -0.7384) -> (6.1438, -0.7384)
  line L616 (-89.1062, -0.7384) -> (-89.1062, -14.8884)
  line L617 (-108.1562, -0.7384) -> (-108.1562, -14.8884)
  line L618 (-89.1062, -0.7384) -> (-74.9562, -14.8884) construction
  line L619 (63.2938, -0.7384) -> (77.4438, -14.8884) construction
  line L620 (77.4438, -0.7384) -> (63.2938, -0.7384)
  line L621 (63.2938, -14.8884) -> (77.4438, -14.8884)
  line L622 (-74.9562, -0.7384) -> (-89.1062, -14.8884) construction
  line L623 (-74.9562, -0.7384) -> (-89.1062, -0.7384)
  line L624 (-89.1062, -14.8884) -> (-74.9562, -14.8884)
  line L625 (77.4438, -0.7384) -> (63.2938, -14.8884) construction
  line L626 (-146.2562, -14.8884) -> (-132.1062, -14.8884)
  line L627 (-146.2562, -0.7384) -> (-132.1062, -14.8884) construction
  line L628 (20.2938, -14.8884) -> (20.2938, -0.7384)
  line L629 (77.4438, -14.8884) -> (77.4438, -0.7384)
  line L630 (58.3938, -14.8884) -> (58.3938, -0.7384)
  line L631 (39.3438, -14.8884) -> (39.3438, -0.7384)
  line L632 (44.2438, -0.7384) -> (58.3938, -14.8884) construction
  line L633 (39.3438, -0.7384) -> (25.1938, -14.8884) construction
  line L634 (-132.1062, -0.7384) -> (-146.2562, -0.7384)
  line L635 (44.2438, -14.8884) -> (58.3938, -14.8884)
  line L636 (44.2438, -0.7384) -> (44.2438, -14.8884)
  line L637 (-132.1062, -0.7384) -> (-146.2562, -14.8884) construction
  line L638 (25.1938, -0.7384) -> (39.3438, -14.8884) construction
  line L639 (39.3438, -0.7384) -> (25.1938, -0.7384)
  line L640 (25.1938, -14.8884) -> (39.3438, -14.8884)
  line L641 (-184.3562, -0.7384) -> (-170.2062, -14.8884) construction
  line L642 (63.2938, -0.7384) -> (63.2938, -14.8884)
  line L643 (-113.0562, -0.7384) -> (-127.2062, -0.7384)
  line L644 (-127.2062, -0.7384) -> (-113.0562, -14.8884) construction
  line L645 (58.3938, -0.7384) -> (44.2438, -0.7384)
  line L646 (-170.2062, -14.8884) -> (-170.2062, -0.7384)
  line L647 (-127.2062, -14.8884) -> (-113.0562, -14.8884)
  line L648 (-17.8062, -0.7384) -> (-31.9562, -0.7384)
  line L649 (58.3938, -0.7384) -> (44.2438, -14.8884) construction
  line L650 (-170.2062, -0.7384) -> (-184.3562, -14.8884) construction
  line L651 (-113.0562, -14.8884) -> (-113.0562, -0.7384)
  line L652 (-127.2062, -0.7384) -> (-127.2062, -14.8884)
  line L653 (-184.3562, -14.8884) -> (-170.2062, -14.8884)
  line L654 (25.1938, -0.7384) -> (25.1938, -14.8884)
  line L655 (-184.3562, -0.7384) -> (-184.3562, -14.8884)
  line L656 (-132.1062, -14.8884) -> (-132.1062, -0.7384)
  line L657 (-113.0562, -0.7384) -> (-127.2062, -14.8884) construction
  line L658 (-151.1562, -0.7384) -> (-165.3062, -0.7384)
  line L659 (-17.8062, -0.7384) -> (-31.9562, -14.8884) construction
  line L660 (-165.3062, -0.7384) -> (-151.1562, -14.8884) construction
  line L661 (-31.9562, -14.8884) -> (-17.8062, -14.8884)
  line L662 (-31.9562, -0.7384) -> (-17.8062, -14.8884) construction
  line L663 (-170.2062, -0.7384) -> (-184.3562, -0.7384)
  line L664 (-151.1562, -0.7384) -> (-165.3062, -14.8884) construction
  line L665 (-146.2562, -0.7384) -> (-146.2562, -14.8884)
  line L666 (-165.3062, -14.8884) -> (-151.1562, -14.8884)
  line L667 (-151.1562, -14.8884) -> (-151.1562, -0.7384)
  line L668 (-12.9062, -0.7384) -> (-12.9062, -14.8884)
  line L669 (-55.9062, -0.7384) -> (-70.0562, -14.8884) construction
  line L670 (-70.0562, -0.7384) -> (-70.0562, -14.8884)
  line L671 (1.2438, -0.7384) -> (-12.9062, -14.8884) construction
  line L672 (-165.3062, -0.7384) -> (-165.3062, -14.8884)
  line L673 (1.2438, -14.8884) -> (1.2438, -0.7384)
  line L674 (-70.0562, -14.8884) -> (-55.9062, -14.8884)
  line L675 (-74.9562, -14.8884) -> (-74.9562, -0.7384)
  line L676 (-55.9062, -14.8884) -> (-55.9062, -0.7384)
  line L677 (-12.9062, -0.7384) -> (1.2438, -14.8884) construction
  line L678 (-55.9062, -0.7384) -> (-70.0562, -0.7384)
  line L679 (-51.0062, -14.8884) -> (-36.8562, -14.8884)
  line L680 (-51.0062, -0.7384) -> (-51.0062, -14.8884)
  line L681 (-12.9062, -14.8884) -> (1.2438, -14.8884)
  line L682 (-17.8062, -14.8884) -> (-17.8062, -0.7384)
  line L683 (-51.0062, -0.7384) -> (-36.8562, -14.8884) construction
  line L684 (-70.0562, -0.7384) -> (-55.9062, -14.8884) construction
  line L685 (6.1438, -0.7384) -> (6.1438, -14.8884)
  line L686 (-36.8562, -0.7384) -> (-51.0062, -14.8884) construction
  line L687 (-36.8562, -14.8884) -> (-36.8562, -0.7384)
  line L688 (-31.9562, -0.7384) -> (-31.9562, -14.8884)
  line L689 (-36.8562, -0.7384) -> (-51.0062, -0.7384)
  line L690 (1.2438, -0.7384) -> (-12.9062, -0.7384)
  line L691 (15.6681, -33.9384) -> (29.8181, -33.9384)
  line L692 (29.8181, -19.7884) -> (15.6681, -19.7884)
  line L693 (-79.5819, -33.9384) -> (-65.4319, -33.9384)
  line L694 (-60.5319, -33.9384) -> (-46.3819, -33.9384)
  line L695 (29.8181, -19.7884) -> (15.6681, -33.9384) construction
  line L696 (15.6681, -19.7884) -> (29.8181, -33.9384) construction
  line L697 (-22.4319, -33.9384) -> (-8.2819, -33.9384)
  line L698 (-98.6319, -33.9384) -> (-84.4819, -33.9384)
  line L699 (34.7181, -33.9384) -> (48.8681, -33.9384)
  line L700 (-22.4319, -19.7884) -> (-22.4319, -33.9384)
  line L701 (10.7681, -19.7884) -> (-3.3819, -33.9384) construction
  line L702 (-3.3819, -19.7884) -> (-3.3819, -33.9384)
  line L703 (-8.2819, -19.7884) -> (-22.4319, -33.9384) construction
  line L704 (-65.4319, -19.7884) -> (-79.5819, -33.9384) construction
  line L705 (-65.4319, -33.9384) -> (-65.4319, -19.7884)
  line L706 (-79.5819, -19.7884) -> (-79.5819, -33.9384)
  line L707 (-122.5819, -19.7884) -> (-136.7319, -33.9384) construction
  line L708 (-27.3319, -33.9384) -> (-27.3319, -19.7884)
  line L709 (-46.3819, -33.9384) -> (-46.3819, -19.7884)
  line L710 (-103.5319, -19.7884) -> (-117.6819, -33.9384) construction
  line L711 (15.6681, -19.7884) -> (15.6681, -33.9384)
  line L712 (-84.4819, -33.9384) -> (-84.4819, -19.7884)
  line L713 (-65.4319, -19.7884) -> (-79.5819, -19.7884)
  line L714 (-27.3319, -19.7884) -> (-41.4819, -33.9384) construction
  line L715 (-41.4819, -19.7884) -> (-41.4819, -33.9384)
  line L716 (-60.5319, -19.7884) -> (-60.5319, -33.9384)
  line L717 (-98.6319, -19.7884) -> (-98.6319, -33.9384)
  line L718 (-22.4319, -19.7884) -> (-8.2819, -33.9384) construction
  line L719 (-3.3819, -19.7884) -> (10.7681, -33.9384) construction
  line L720 (-3.3819, -33.9384) -> (10.7681, -33.9384)
  line L721 (48.8681, -19.7884) -> (34.7181, -33.9384) construction
  line L722 (-84.4819, -19.7884) -> (-98.6319, -19.7884)
  line L723 (-98.6319, -19.7884) -> (-84.4819, -33.9384) construction
  line L724 (34.7181, -19.7884) -> (34.7181, -33.9384)
  line L725 (-84.4819, -19.7884) -> (-98.6319, -33.9384) construction
  line L726 (29.8181, -33.9384) -> (29.8181, -19.7884)
  line L727 (-41.4819, -33.9384) -> (-27.3319, -33.9384)
  line L728 (34.7181, -19.7884) -> (48.8681, -33.9384) construction
  line L729 (48.8681, -33.9384) -> (48.8681, -19.7884)
  line L730 (10.7681, -33.9384) -> (10.7681, -19.7884)
  line L731 (-79.5819, -19.7884) -> (-65.4319, -33.9384) construction
  line L732 (-41.4819, -19.7884) -> (-27.3319, -33.9384) construction
  line L733 (-60.5319, -19.7884) -> (-46.3819, -33.9384) construction
  line L734 (-8.2819, -33.9384) -> (-8.2819, -19.7884)
  line L735 (-27.3319, -19.7884) -> (-41.4819, -19.7884)
  line L736 (48.8681, -19.7884) -> (34.7181, -19.7884)
  line L737 (-46.3819, -19.7884) -> (-60.5319, -19.7884)
  line L738 (-46.3819, -19.7884) -> (-60.5319, -33.9384) construction
  line L739 (10.7681, -19.7884) -> (-3.3819, -19.7884)
  line L740 (-8.2819, -19.7884) -> (-22.4319, -19.7884)
  line L741 (-117.6819, -19.7884) -> (-103.5319, -33.9384) construction
  line L742 (-122.5819, -33.9384) -> (-122.5819, -19.7884)
  line L743 (-136.7319, -19.7884) -> (-136.7319, -33.9384)
  line L744 (-117.6819, -19.7884) -> (-117.6819, -33.9384)
  line L745 (-136.7319, -19.7884) -> (-122.5819, -33.9384) construction
  line L746 (-103.5319, -33.9384) -> (-103.5319, -19.7884)
  line L747 (-117.6819, -33.9384) -> (-103.5319, -33.9384)
  line L748 (-103.5319, -19.7884) -> (-117.6819, -19.7884)
  line L749 (-136.7319, -33.9384) -> (-122.5819, -33.9384)
  line L750 (-122.5819, -19.7884) -> (-136.7319, -19.7884)
  line L751 (115.5438, -33.9384) -> (115.5438, -19.7884)
  line L752 (96.4938, -19.7884) -> (82.3438, -33.9384) construction
  line L753 (101.3938, -33.9384) -> (115.5438, -33.9384)
  line L754 (115.5438, -19.7884) -> (101.3938, -33.9384) construction
  line L755 (96.4938, -33.9384) -> (96.4938, -19.7884)
  line L756 (101.3938, -19.7884) -> (115.5438, -33.9384) construction
  line L757 (96.4938, -19.7884) -> (82.3438, -19.7884)
  line L758 (82.3438, -19.7884) -> (82.3438, -33.9384)
  line L759 (115.5438, -19.7884) -> (101.3938, -19.7884)
  line L760 (101.3938, -19.7884) -> (101.3938, -33.9384)
  line L761 (82.3438, -19.7884) -> (96.4938, -33.9384) construction
  line L762 (82.3438, -33.9384) -> (96.4938, -33.9384)
  line L763 (-184.3562, -19.7884) -> (-184.3562, -33.9384)
  line L764 (-170.2062, -19.7884) -> (-184.3562, -33.9384) construction
  line L765 (-170.2062, -33.9384) -> (-170.2062, -19.7884)
  line L766 (-184.3562, -33.9384) -> (-170.2062, -33.9384)
  line L767 (-170.2062, -19.7884) -> (-184.3562, -19.7884)
  line L768 (-184.3562, -19.7884) -> (-170.2062, -33.9384) construction
  line L769 (-146.3942, -19.7884) -> (-160.5442, -19.7884)
  line L770 (-146.3933, -33.9378) -> (-160.5442, -33.9378)
  line L771 (-146.3933, -19.7884) -> (-146.3933, -33.9378)
  line L772 (-160.5442, -19.7884) -> (-146.3933, -19.7884)
  line L773 (-160.5442, -33.9378) -> (-160.5442, -19.7884)
  line L774 (-160.5442, -19.7884) -> (-160.5442, -33.9384)
  line L775 (-160.5442, -33.9384) -> (-146.3942, -33.9384)
  line L776 (-146.3942, -33.9384) -> (-146.3942, -19.7884)
  line L777 (-146.3942, -19.7884) -> (-160.5442, -33.9384) construction
  line L778 (-160.5442, -19.7884) -> (-146.3942, -33.9384) construction
  line L779 (72.6801, -19.7884) -> (58.5301, -33.9384) construction
  line L780 (72.6801, -33.9384) -> (72.6801, -19.7884)
  line L781 (58.5301, -19.7884) -> (72.6801, -33.9384) construction
  line L782 (58.5301, -19.7884) -> (58.5301, -33.9384)
  line L783 (72.6801, -19.7884) -> (58.5301, -19.7884)
  line L784 (58.5301, -33.9384) -> (72.6801, -33.9384)
  line L785 (-27.3319, -38.8384) -> (-41.4819, -38.8384)
  line L786 (-41.4819, -52.9884) -> (-27.3319, -52.9884)
  line L787 (-41.4819, -38.8384) -> (-41.4819, -52.9884)
  line L788 (-27.3319, -38.8384) -> (-41.4819, -52.9884) construction
  line L789 (-27.3319, -52.9884) -> (-27.3319, -38.8384)
  line L790 (-41.4819, -38.8384) -> (-27.3319, -52.9884) construction
  line L791 (25.094, -48.2122) -> (-27.3319, -48.2122)
  line L792 (91.8678, -0.7384) -> (91.8678, -14.8884)
  line L793 (91.8678, -14.8884) -> (106.0178, -14.8884)
  line L794 (106.0178, -14.8884) -> (106.0178, -0.7384)
  line L795 (106.0178, -0.7384) -> (91.8678, -14.8884) construction
  line L796 (106.0178, -0.7384) -> (91.8678, -0.7384)
  line L797 (91.8678, -0.7384) -> (106.0178, -14.8884) construction
  line L798 (158.4058, -19.7884) -> (144.2558, -19.7884)
  line L799 (144.2558, -19.7884) -> (144.2558, -33.9384)
  line L800 (158.4058, -33.9384) -> (158.4058, -19.7884)
  line L801 (144.2558, -19.7884) -> (158.4058, -33.9384) construction
  line L802 (158.4058, -19.7884) -> (144.2558, -33.9384) construction
  line L803 (144.2558, -33.9384) -> (158.4058, -33.9384)
  line L804 (191.8798, -24.4124) -> (206.0298, -24.4124)
  line L805 (206.0298, -10.2624) -> (191.8798, -24.4124) construction
  line L806 (206.0298, -24.4124) -> (206.0298, -10.2624)
  line L807 (206.0298, -10.2624) -> (191.8798, -10.2624)
  line L808 (191.8798, -10.2624) -> (206.0298, -24.4124) construction
  line L809 (191.8798, -10.2624) -> (191.8798, -24.4124)
  line L810 (-98.5306, -40.3822) -> (-98.5306, -39.1822)
  line L811 (-95.2306, -40.3822) -> (-95.2306, -39.1822)
  line L812 (-98.5306, -39.1822) -> (-95.2306, -39.1822)
  line L813 (26.8195, -39.1822) -> (30.1195, -39.1822)
  line L814 (26.819, -40.3822) -> (26.8195, -39.1822)
  line L815 (-100.2556, -40.3822) -> (-98.5306, -40.3822)
  line L816 (-95.2306, -40.3822) -> (-93.5059, -40.3822)
  line L817 (30.1195, -39.1822) -> (30.1195, -40.3822)
  line L818 (25.094, -40.3822) -> (26.819, -40.3822)
  line L819 (30.1195, -40.3822) -> (31.844, -40.3822)
  line L820 (25.094, -52.6826) -> (31.844, -52.6826)
  circle A16 centre (-149.4049, -49.818) radius 2.5
  circle A17 centre (171.032, -49.8176) radius 2.5
  circle A18 centre (10.8715, 59.2108) radius 2.5
  point P0 (158.632, 71.958)
  point P1 (-177.2812, 59.85)
  point P2 (-177.2812, 30.2866)
  point P3 (-172.4989, 11.2366)
  point P4 (-158.2312, 59.85)
  point P5 (-139.1812, 59.85)
  point P6 (-120.1312, 59.85)
  point P7 (-177.2812, 59.85)
  point P8 (-139.1812, 59.85)
  point P9 (-158.2312, 59.85)
  point P10 (-120.1312, 59.85)
  point P11 (-24.8812, 59.85)
  point P12 (-5.8312, 59.85)
  point P13 (-62.9812, 59.85)
  point P14 (-43.9312, 59.85)
  point P15 (-5.8312, 59.85)
  point P16 (-62.9812, 59.85)
  point P17 (-43.9312, 59.85)
  point P18 (-24.8812, 59.85)
  point P19 (89.4188, 59.85)
  point P20 (108.4688, 59.85)
  point P21 (51.3188, 59.85)
  point P22 (70.3688, 59.85)
  point P23 (108.4688, 59.85)
  point P24 (51.3188, 59.85)
  point P25 (70.3688, 59.85)
  point P26 (89.4188, 59.85)
  point P27 (160.8548, 59.85)
  point P28 (179.9048, 59.85)
  point P29 (198.9548, 59.85)
  point P30 (141.8048, 59.85)
  point P31 (179.9048, 59.85)
  point P32 (198.9548, 59.85)
  point P33 (141.8048, 59.85)
  point P34 (160.8548, 59.85)